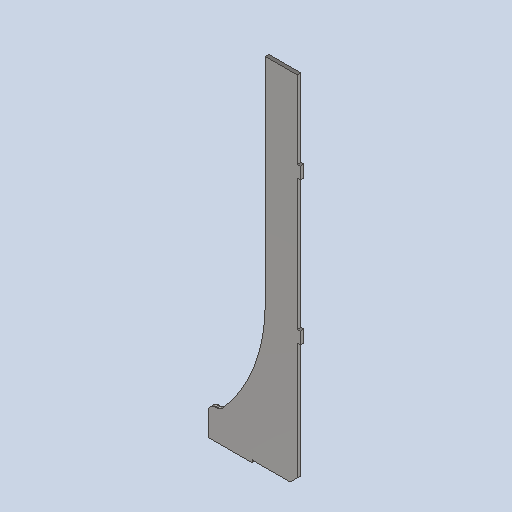
# Autodesk Inventor part: DMF-1206 Slot Plate Large 01
Saved by Autodesk Inventor 2026.2 (Build 302298000, 298)
## iProperties
Created: 2024-04-30
Part Number: DMF-1206 Slot Plate Large 01
Material: Stainless Steel
Document SubType Name: Sheet Metal
Designer: pokla
Density: 8 g/cm^3
Sheet Metal Rule: Default
Sheet Metal Width: 77,500 mm
Sheet Metal Length: 301,000 mm
Sheet Metal Area: 23327,500 mm^2
Appearance: Semi-Polished
Flat Pattern Width: 7.75 cm
Flat Pattern Length: 30.1 cm
Flat Pattern Area: 233.275 cm^2
Stock Number: DMF-1206
Mass: 30.2951 g
Surface Area: 223.238 cm^2
Volume: 30.2951 cm^3
Author: pokla
Autodesk Inventor part; units mm, degrees
ref_plane "YZ Plane" through (0, 0, 0) normal (1, 0, 0) x (0, 1, 0)
ref_plane "XZ Plane" through (0, 0, 0) normal (0, 1, 0) x (-1, 0, 0)
ref_plane "XY Plane" through (0, 0, 0) normal (0, 0, 1) x (1, 0, 0)
sketch "Sketch1" plane through (0, 0, 0) normal (0, 0, 1) x (1, 0, 0)
  line L0 (0, 0) -> (-38, 0)
  line L1 (-38, 0) -> (-38, 2)
  line L2 (-38, 2) -> (0, 2)
  line L3 (0, 2) -> (0, 0)
  line L4 (0, 2) -> (0, 301)
  line L5 (0, 301) -> (-27, 301)
  line L6 (-27, 301) -> (-75, 25)
  line L7 (-75, 25) -> (-75, 0)
  line L8 (-75, 0) -> (-38, 0)
  line L9 (-27, 301) -> (-27, 121)
  line L10 (-75, 25) -> (-65, 25)
  arc A0 (-65, 25) -> (-27, 121) centre (-167.2632, 121) ccw
  line L11 (0, 236) -> (2.5, 236)
  line L12 (2.5, 236) -> (2.5, 226)
  line L13 (2.5, 226) -> (0, 226)
  line L14 (0, 226) -> (0, 236)
  line L15 (0, 116) -> (2.5, 116)
  line L16 (2.5, 116) -> (2.5, 106)
  line L17 (2.5, 106) -> (0, 106)
  line L18 (0, 106) -> (0, 116)
  point P0 (2.5, 111)
  point P1 (2.5, 231)
  point P2 (0, 226)
  dimension "d65" = 38
  dimension "d66" = 2
  dimension "d77" = 299
  dimension "d78" = 25
  dimension "d80" = 27
  dimension "d94" = 180
  dimension "d102" = 10
  dimension "d104" = 75
  dimension "d105" = 2.5
  dimension "d106" = 10
  dimension "d107" = 10
  dimension "d108" = 120
  dimension "d109" = 70
  measures "d65" distance of L1.end L2.end
  measures "d66" distance of L0.end L1.end
  measures "d77" distance of L2.end L4.end
  measures "d78" distance of L6.end L7.end
  measures "d80" distance of L4.end L5.end
  measures "d94" distance of L5.end L9.end
  measures "d102" distance of L6.end L10.end
  measures "d104" distance between parallel lines of L7 L4
  measures "d105" distance of L12.end L13.end
  measures "d106" distance of L15.end L16.end
  measures "d107" distance of L11.end L12.end
  measures "d108" distance of point (2.5, 111) point (2.5, 231)
  measures "d109" distance from line of L5 point (2.5, 231)
extrude "Plate1" add sketch "Sketch1" along normal mid plane 3 contours L8 L7 L10 A0 L9 L5 L4 L2 L1 | L4 L15 L16 L17 | L4 L11 L12 L13
chamfer "Corner Chamfer5" distance 6 angle 45 1 edges at (0, 2, 0)
fillet "Corner Round1" radius 6 2 edges at (-65, 25, 0) (-75, 25, 0)
equation "\"d15\" = Thickness"
equation "\"BendRadius\" = Thickness"
equation "\"BendReliefWidth\" = Thickness"
equation "\"BendReliefDepth\" = 0.5 * Thickness"
equation "\"CornerReliefSize\" = 4 * Thickness"
equation "\"MinimumRemnant\" = 2 * Thickness"
equation "\"TransitionRadius\" = BendRadius"
equation "\"JacobiRadiusSize\" = BendRadius"
equation "\"GapSize\" = Thickness"
equation "\"Thickness\" = 3"
body "Solid1"
